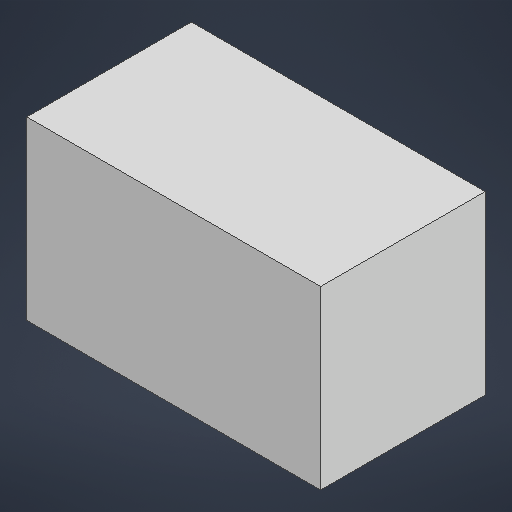
# Autodesk Inventor part: ElectricityBoxModel
Saved by Autodesk Inventor 2027.1 (Build 311270010, 270A)
## iProperties
Created: 2026-10-13
Part Number: ElectricityBoxModel
Material: Generic
Document SubType Name: Modeling
Designer: SDS Scholar
Density: 1 g/cm^3
Appearance: Default
Author: SDS Scholar
Autodesk Inventor part; units mm, degrees
ref_plane "YZ Plane" through (0, 0, 0) normal (1, 0, 0) x (0, 1, 0)
ref_plane "XZ Plane" through (0, 0, 0) normal (0, 1, 0) x (-1, 0, 0)
ref_plane "XY Plane" through (0, 0, 0) normal (0, 0, 1) x (1, 0, 0)
sketch "Sketch1" plane through (0, 0, 0) normal (0, 1, 0) x (-1, 0, 0)
  line L0 (125, 70) -> (-125, 70)
  line L1 (-125, 70) -> (-125, -70)
  line L2 (-125, -70) -> (125, -70)
  line L3 (125, -70) -> (125, 70)
  point P0 (0, 0)
  point P1 (125, 0)
  point P2 (0, -70)
  dimension "d0" = 140
  dimension "d1" = 250
  constraints: 8 end point, 2 midpoint, 2 parallel, 1 horizontal, 1 horizontal alignment, 1 perpendicular, 1 vertical alignment
  measures "d0" distance of L2.end L0.start
  measures "d1" distance of L1.end L2.end
extrude "Extrusion1" add sketch "Sketch1" along normal blind 150
sketch "Sketch2" plane through (0, 0, 0) normal (0, -1, 0) x (1, 0, 0)
  line L0 (125, 70) -> (125, -70) projected
  line L1 (-125, 70) -> (125, 70) projected
  line L2 (-125, -70) -> (-125, 70) projected
  line L3 (125, -70) -> (-125, -70) projected
  line L4 (-122, -67) -> (-122, 67)
  line L5 (-122, 67) -> (122, 67)
  line L6 (122, 67) -> (122, -67)
  line L7 (122, -67) -> (-122, -67)
  point P0 (0, 0)
  dimension "d4" = 3
  constraints: 8 end point, 3 other
  measures "d4" distance between parallel lines of L3 L7
extrude "Extrusion2" cut sketch "Sketch2" against normal blind 147 contours L4 L5 L6 L7
body "Solid1"
